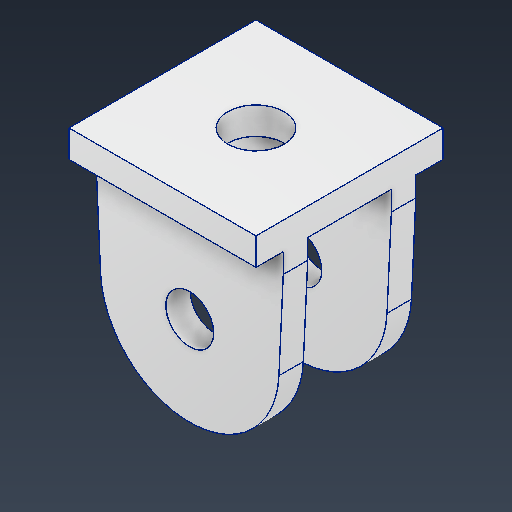
# Autodesk Inventor part: CYLINDER FIXING PARTS_B PARTS
Saved by Autodesk Inventor 2026.2 (Build 302298010, 298A)
## iProperties
Created: 2026-05-13
Part Number: CYLINDER FIXING PARTS_B PARTS
Material: 알루미늄 6061
Document SubType Name: Modeling
Designer: khw
Density: 2.7 g/cm^3
Appearance: 알루미늄 - 평지
Mass: 7.65613 g
Surface Area: 26.335 cm^2
Volume: 2.8356 cm^3
Author: khw
Autodesk Inventor part; units mm, degrees
ref_plane "YZ Plane" through (0, 0, 0) normal (1, 0, 0) x (0, 1, 0)
ref_plane "XZ Plane" through (0, 0, 0) normal (0, 1, 0) x (-1, 0, 0)
ref_plane "XY Plane" through (0, 0, 0) normal (0, 0, 1) x (1, 0, 0)
sketch "스케치1" plane through (0, 0, 0) normal (0, 0, 1) x (1, 0, 0)
  circle A0 centre (0, 0) radius 2.55
  line L0 (0, 0) -> (0, 14.1)
  line L1 (-9.95, 14.1) -> (9.95, 14.1)
  circle A1 centre (0, 0) radius 9.5
  line L2 (9.95, 14.1) -> (9.95, 9.1)
  line L3 (-9.95, 14.1) -> (-9.95, 9.1)
  line L4 (-9.95, 9.1) -> (-9.489, -0.4577)
  line L5 (9.95, 9.1) -> (9.489, -0.4577)
  point P0 (-9.4953, -0.2999)
  dimension "d0" = 5.1
  dimension "d1" = 14.1
  dimension "d2" = 19.9
  dimension "d3" = 23.6
  dimension "d20" = 5
  dimension "d21" = 5
  constraints: 12 end point, 3 point on circle, 3 vertical, 2 centre point, 2 coincident, 2 tangent, 1 horizontal, 1 midpoint
  measures "d0" diameter of A0
  measures "d1" distance of L0.start L0.end
  measures "d2" distance of L1.start L1.end
  measures "d20" distance of L1.end L2.end
  measures "d21" distance of L1.start L3.end
extrude "돌출1" add sketch "스케치1" along normal blind 19.9
sketch "스케치2" plane through (0, 0, 0) normal (1, 0, 0) x (0, 1, 0)
  line L0 (14.1, 0) -> (-0.2999, 0) projected
  line L1 (-0.2999, 0) -> (-0.2999, 19.9) projected
  line L2 (14.1, 19.9) -> (-0.2999, 19.9) projected
  line L3 (14.1, 0) -> (14.1, 19.9) projected
  line L4 (-0.4577, 0) -> (-0.4577, 0) projected
  line L5 (-0.4577, 19.9) -> (-0.4577, 19.9) projected
  line L6 (14.1, 9.95) -> (-16.5005, 9.95) construction
  line L7 (11.2, 17) -> (-16.5005, 17)
  line L8 (-16.5005, 17) -> (-16.5005, 2.9)
  line L9 (-16.5005, 2.9) -> (11.2, 2.9)
  line L10 (11.2, 2.9) -> (11.2, 17)
  line L11 (-0.4577, 19.9) -> (-0.4577, 19.9) projected
  line L12 (-2.55, 19.9) -> (2.55, 19.9) projected
  line L13 (11.2, 29.95) -> (-16.5005, 29.95)
  line L14 (-16.5005, 29.95) -> (-16.5005, -10.05)
  line L15 (-16.5005, -10.05) -> (11.2, -10.05)
  line L16 (11.2, -10.05) -> (11.2, 29.95)
  line L17 (11.2, 5.5) -> (-16.5005, 5.5)
  line L18 (-16.5005, 5.5) -> (-16.5005, 14.4)
  line L19 (-16.5005, 14.4) -> (11.2, 14.4)
  line L20 (11.2, 14.4) -> (11.2, 5.5)
  line L21 (-0.4577, 19.9) -> (9.1, 19.9) projected
  line L22 (9.1, 19.9) -> (14.1, 19.9) projected
  line L23 (14.1, 19.9) -> (9.1, 19.9) projected
  line L24 (9.1, 19.9) -> (-0.4577, 19.9) projected
  line L25 (-0.4577, 0) -> (-0.4577, 19.9) projected
  line L26 (-0.4577, 0) -> (-0.4577, 19.9) projected
  point P0 (0, 0)
  point P1 (9.5, 0)
  point P2 (-9.5, 0)
  point P3 (-9.5, 19.9)
  point P4 (9.5, 19.9)
  point P5 (-9.5, 19.9)
  point P6 (9.5, 19.9)
  point P7 (11.2, 9.95)
  point P8 (-16.5005, 17)
  point P9 (11.2, 2.9)
  point P10 (-16.5005, 5.5)
  dimension "d6" = 14.1
  dimension "d7" = 2.9
  dimension "d16" = 40
  dimension "d17" = 27.7005
  dimension "d18" = 2.6
  dimension "d19" = 0
  constraints: 26 end point, 7 midpoint, 6 parallel, 4 horizontal, 3 perpendicular, 1 point on line
  measures "d6" distance of L8.end L7.end
  measures "d7" distance between parallel lines of L3 L10
  measures "d16" distance of L13.end L14.end
  measures "d17" distance of L14.end L15.end
  measures "d18" distance between parallel lines of L9 L17
  measures "d19" distance between parallel lines of L14 L18
extrude "돌출2" cut sketch "스케치2" along normal through all both and the other way through all contours L16 L15 L14 L9 L1 L0 | L0 L1 L9 L16 | L16 L7 L1 L2 | L2 L12 L25 L7 L14 L13 L16 | L17 L1 L19 L10 | L17 L25 L19 L1 | L7 L25 L12 L1 | L17 L8 L19 L25
sketch "스케치3" plane through (-9.95, 14.1, 0) normal (0, 1, 0) x (1, 0, 0)
  line L0 (19.9, 0) -> (0, 0) projected
  line L1 (0, 0) -> (0, -19.9) projected
  line L2 (19.9, -19.9) -> (0, -19.9) projected
  line L3 (19.9, 0) -> (19.9, -19.9) projected
  line L4 (0, -9.95) -> (19.9, -9.95) construction
  circle A0 centre (9.95, -9.95) radius 3
  point P0 (9.95, 0)
  dimension "d10" = 6
  constraints: 3 midpoint, 2 end point, 1 centre point
  measures "d10" diameter of A0
extrude "돌출3" cut sketch "스케치3" against normal through all contours A0
